Autodesk Fusion 360 part; units mm, degrees
(part 3 of 3)
  line L518 (103.505, 148.65858) -> (102.6922, 148.65858)
  line L519 (137.3378, 134.70636) -> (137.3378, 131.20624)
  line L520 (140.7922, 63.94958) -> (140.7922, 67.4497)
  line L521 (155.575, 76.93914) -> (155.575, 75.9587)
  line L522 (159.8422, 126.43358) -> (159.8422, 129.9337)
  line L523 (122.555, 135.6868) -> (136.525, 135.6868)
  line L524 (137.3378, 131.20624) -> (136.525, 131.20624)
  line L525 (155.575, 67.4497) -> (156.3878, 67.4497)
  line L526 (160.655, 130.91414) -> (174.625, 130.91414)
  line L527 (155.575, 75.9587) -> (156.3878, 75.9587)
  line L528 (155.575, 72.45858) -> (155.575, 67.4497)
  line L529 (136.525, 154.7368) -> (136.525, 153.75636)
  line L530 (136.525, 145.24736) -> (137.3378, 145.24736)
  line L531 (160.655, 126.43358) -> (159.8422, 126.43358)
  line L532 (136.525, 134.70636) -> (137.3378, 134.70636)
  line L533 (103.505, 152.1587) -> (103.505, 153.13914)
  line L534 (140.7922, 67.4497) -> (141.605, 67.4497)
  line L535 (140.7922, 75.9587) -> (141.605, 75.9587)
  line L536 (141.605, 67.4497) -> (141.605, 72.45858)
  line L537 (141.605, 76.93914) -> (155.575, 76.93914)
  line L538 (117.475, 139.16914) -> (103.505, 139.16914)
  line L539 (160.655, 117.92458) -> (159.8422, 117.92458)
  line L540 (118.2878, 152.1587) -> (118.2878, 148.65858)
  line L541 (118.2878, 143.6497) -> (118.2878, 140.14958)
  line L542 (175.4378, 129.9337) -> (175.4378, 126.43358)
  line L543 (174.625, 117.92458) -> (174.625, 116.94414)
  line L544 (117.475, 143.6497) -> (118.2878, 143.6497)
  line L545 (117.475, 148.65858) -> (117.475, 143.6497)
  line L546 (103.505, 140.14958) -> (102.6922, 140.14958)
  line L547 (174.625, 116.94414) -> (160.655, 116.94414)
  line L548 (160.655, 121.4247) -> (160.655, 126.43358)
  line L549 (141.605, 62.96914) -> (141.605, 63.94958)
  line L550 (117.475, 140.14958) -> (117.475, 139.16914)
  line L551 (102.6922, 152.1587) -> (103.505, 152.1587)
  line L552 (102.6922, 143.6497) -> (103.505, 143.6497)
  line L553 (103.505, 143.6497) -> (103.505, 148.65858)
  line L554 (155.575, 63.94958) -> (155.575, 62.96914)
  line L555 (117.475, 152.1587) -> (118.2878, 152.1587)
  line L556 (141.605, 75.9587) -> (141.605, 76.93914)
  line L557 (174.625, 121.4247) -> (175.4378, 121.4247)
  line L558 (103.505, 139.16914) -> (103.505, 140.14958)
  line L559 (174.625, 129.9337) -> (175.4378, 129.9337)
  line L560 (156.3878, 75.9587) -> (156.3878, 72.45858)
  line L561 (175.4378, 117.92458) -> (174.625, 117.92458)
  line L562 (159.8422, 117.92458) -> (159.8422, 121.4247)
  line L563 (136.525, 135.6868) -> (136.525, 134.70636)
  line L564 (118.2878, 148.65858) -> (117.475, 148.65858)
  line L565 (102.6922, 140.14958) -> (102.6922, 143.6497)
  line L566 (141.605, 63.94958) -> (140.7922, 63.94958)
  line L567 (141.605, 72.45858) -> (140.7922, 72.45858)
  line L568 (174.625, 130.91414) -> (174.625, 129.9337)
  line L569 (156.3878, 63.94958) -> (155.575, 63.94958)
  line L570 (159.8422, 121.4247) -> (160.655, 121.4247)
  line L571 (156.3878, 67.4497) -> (156.3878, 63.94958)
  line L572 (159.8422, 129.9337) -> (160.655, 129.9337)
  line L573 (159.8422, 110.8837) -> (160.655, 110.8837)
  line L574 (156.3878, 114.0587) -> (156.3878, 110.55858)
  line L575 (122.555, 122.69724) -> (121.7422, 122.69724)
  line L576 (118.2878, 133.1087) -> (118.2878, 129.60858)
  line L577 (117.475, 121.09958) -> (117.475, 120.11914)
  line L578 (121.7422, 134.70636) -> (122.555, 134.70636)
  line L579 (118.2878, 129.60858) -> (117.475, 129.60858)
  line L580 (160.655, 102.3747) -> (160.655, 107.38358)
  line L581 (121.7422, 131.20624) -> (121.7422, 134.70636)
  line L582 (118.2878, 124.5997) -> (118.2878, 121.09958)
  line L583 (65.405, 151.8666) -> (79.375, 151.8666)
  line L584 (79.375, 138.87704) -> (79.375, 137.8966)
  line L585 (74.89444, 113.27384) -> (74.89444, 114.08664)
  line L586 (65.405, 114.08664) -> (65.405, 128.05664)
  line L587 (66.38544, 113.27384) -> (66.38544, 114.08664)
  line L588 (98.425, 119.82958) -> (98.425, 118.84914)
  line L589 (74.89444, 100.29444) -> (78.39456, 100.29444)
  line L590 (194.4878, 69.28358) -> (193.675, 69.28358)
  line L591 (83.6422, 123.3297) -> (84.455, 123.3297)
  line L592 (69.88556, 128.05664) -> (74.89444, 128.05664)
  line L593 (66.38544, 114.08664) -> (65.405, 114.08664)
  line L594 (78.39456, 84.69884) -> (74.89444, 84.69884)
  line L595 (65.405, 150.88616) -> (65.405, 151.8666)
  line L596 (65.405, 128.05664) -> (66.38544, 128.05664)
  line L597 (78.39456, 100.29444) -> (78.39456, 99.48164)
  line L598 (194.4878, 60.77458) -> (193.675, 60.77458)
  line L599 (79.375, 99.48164) -> (79.375, 85.51164)
  line L600 (69.88556, 84.69884) -> (66.38544, 84.69884)
  line L601 (178.8922, 60.77458) -> (178.8922, 64.2747)
  line L602 (179.705, 59.79414) -> (179.705, 60.77458)
  line L603 (178.8922, 69.28358) -> (178.8922, 72.7837)
  line L604 (98.425, 131.8387) -> (99.2378, 131.8387)
  line L605 (84.455, 131.8387) -> (84.455, 132.81914)
  line L606 (98.425, 128.33858) -> (98.425, 123.3297)
  line L607 (80.1878, 142.37716) -> (80.1878, 138.87704)
  line L608 (78.39456, 85.51164) -> (78.39456, 84.69884)
  line L609 (194.4878, 64.2747) -> (194.4878, 60.77458)
  line L610 (69.88556, 85.51164) -> (69.88556, 84.69884)
  line L611 (69.88556, 128.86944) -> (69.88556, 128.05664)
  line L612 (193.675, 73.76414) -> (193.675, 72.7837)
  line L613 (83.6422, 128.33858) -> (83.6422, 131.8387)
  line L614 (69.88556, 100.29444) -> (69.88556, 99.48164)
  line L615 (46.54042, 57.84342) -> (47.27702, 58.18632)
  line L616 (179.705, 64.2747) -> (179.705, 69.28358)
  line L617 (83.6422, 131.8387) -> (84.455, 131.8387)
  line L618 (50.13706, 50.13198) -> (50.87366, 50.47488)
  line L619 (52.0319, 46.07052) -> (39.37, 40.16502)
  line L620 (39.37, 40.16502) -> (38.95598, 41.05402)
  line L621 (38.21938, 40.71112) -> (36.73856, 43.88358)
  line L622 (84.455, 118.84914) -> (84.455, 119.82958)
  line L623 (99.2378, 123.3297) -> (99.2378, 119.82958)
  line L624 (84.455, 128.33858) -> (83.6422, 128.33858)
  line L625 (38.95598, 41.05402) -> (38.21938, 40.71112)
  line L626 (193.675, 59.79414) -> (179.705, 59.79414)
  line L627 (79.375, 85.51164) -> (78.39456, 85.51164)
  line L628 (52.35194, 47.30242) -> (51.61534, 46.95952)
  line L629 (99.2378, 131.8387) -> (99.2378, 128.33858)
  line L630 (74.89444, 84.69884) -> (74.89444, 85.51164)
  line L631 (194.4878, 72.7837) -> (194.4878, 69.28358)
  line L632 (193.675, 64.2747) -> (194.4878, 64.2747)
  line L633 (74.89444, 85.51164) -> (69.88556, 85.51164)
  line L634 (84.455, 132.81914) -> (98.425, 132.81914)
  line L635 (98.425, 118.84914) -> (84.455, 118.84914)
  line L636 (50.87366, 50.47488) -> (52.35194, 47.30242)
  line L637 (178.8922, 72.7837) -> (179.705, 72.7837)
  line L638 (46.27118, 23.4442) -> (44.79036, 26.61666)
  line L639 (48.02124, 54.67096) -> (50.13706, 50.13198)
  line L640 (56.07304, 37.40404) -> (58.18886, 32.86506)
  line L641 (60.40374, 30.0355) -> (59.66714, 29.6926)
  line L642 (39.97198, 71.93534) -> (42.0878, 67.39636)
  line L643 (31.32074, 57.4294) -> (30.90672, 58.3184)
  line L644 (46.1264, 58.73242) -> (46.54042, 57.84342)
  line L645 (193.675, 69.28358) -> (193.675, 64.2747)
  line L646 (84.455, 119.82958) -> (83.6422, 119.82958)
  line L647 (99.2378, 128.33858) -> (98.425, 128.33858)
  line L648 (98.425, 132.81914) -> (98.425, 131.8387)
  line L649 (33.4645, 52.82692) -> (46.1264, 58.73242)
  line L650 (179.705, 60.77458) -> (178.8922, 60.77458)
  line L651 (30.90672, 58.3184) -> (30.17012, 57.9755)
  line L652 (58.92546, 33.20796) -> (60.40374, 30.0355)
  line L653 (193.675, 60.77458) -> (193.675, 59.79414)
  line L654 (48.58512, 65.47866) -> (48.1711, 66.36766)
  line L655 (48.1711, 66.36766) -> (47.4345, 66.02476)
  line L656 (56.80964, 37.74694) -> (56.07304, 37.40404)
  line L657 (178.8922, 64.2747) -> (179.705, 64.2747)
  line L658 (84.455, 123.3297) -> (84.455, 128.33858)
  line L659 (47.27702, 58.18632) -> (48.75784, 55.01386)
  line L660 (83.6422, 119.82958) -> (83.6422, 123.3297)
  line L661 (179.705, 73.76414) -> (193.675, 73.76414)
  line L662 (48.75784, 55.01386) -> (48.02124, 54.67096)
  line L663 (66.38544, 84.69884) -> (66.38544, 85.51164)
  line L664 (51.61534, 46.95952) -> (52.0319, 46.07052)
  line L665 (193.675, 72.7837) -> (194.4878, 72.7837)
  line L666 (66.38544, 85.51164) -> (65.405, 85.51164)
  line L667 (98.425, 123.3297) -> (99.2378, 123.3297)
  line L668 (179.705, 72.7837) -> (179.705, 73.76414)
  line L669 (179.705, 69.28358) -> (178.8922, 69.28358)
  line L670 (99.2378, 119.82958) -> (98.425, 119.82958)
  line L671 (41.5163, 35.56) -> (54.1782, 41.4655)
  line L672 (28.6893, 61.14796) -> (29.4259, 61.49086)
  line L673 (30.17012, 57.9755) -> (28.6893, 61.14796)
  line L674 (35.35934, 48.76546) -> (34.62274, 48.42256)
  line L675 (57.97296, 80.3275) -> (57.23636, 79.9846)
  line L676 (34.62274, 48.42256) -> (33.14446, 51.59502)
  line L677 (61.56706, 72.61606) -> (60.83046, 72.27316)
  line L678 (42.0878, 67.39636) -> (42.8244, 67.73926)
  line L679 (60.83046, 72.27316) -> (61.24702, 71.38416)
  line L680 (55.32882, 40.9194) -> (56.80964, 37.74694)
  line L681 (61.24702, 71.38416) -> (48.58512, 65.47866)
  line L682 (55.75554, 83.15706) -> (56.49214, 83.49996)
  line L683 (38.49116, 75.1078) -> (39.22776, 75.4507)
  line L684 (45.52696, 26.95956) -> (43.41114, 31.49854)
  line L685 (33.14446, 51.59502) -> (33.88106, 51.93792)
  line L686 (27.31008, 66.02984) -> (26.57348, 65.68694)
  line L687 (26.57348, 65.68694) -> (25.0952, 68.8594)
  line L688 (43.83786, 73.7362) -> (42.35958, 76.90866)
  line L689 (56.49214, 83.49996) -> (57.97296, 80.3275)
  line L690 (44.79036, 26.61666) -> (45.52696, 26.95956)
  line L691 (41.19626, 34.3281) -> (41.93286, 34.671)
  line L692 (41.93286, 34.671) -> (41.5163, 35.56)
  line L693 (60.0837, 28.8036) -> (47.4218, 22.8981)
  line L694 (59.35218, 75.44562) -> (60.08878, 75.78852)
  line L695 (37.47516, 44.22648) -> (35.35934, 48.76546)
  line L696 (43.56608, 64.2239) -> (43.98264, 63.3349)
  line L697 (25.8318, 69.2023) -> (25.41524, 70.0913)
  line L698 (155.575, 140.14958) -> (155.575, 139.16914)
  line L699 (42.67962, 78.14056) -> (55.34152, 84.04606)
  line L700 (44.57446, 74.0791) -> (43.83786, 73.7362)
  line L701 (25.0952, 68.8594) -> (25.8318, 69.2023)
  line L702 (38.07714, 75.9968) -> (38.49116, 75.1078)
  line L703 (121.7422, 153.75636) -> (122.555, 153.75636)
  line L704 (156.3878, 140.14958) -> (155.575, 140.14958)
  line L705 (29.4259, 61.49086) -> (27.31008, 66.02984)
  line L706 (55.34152, 84.04606) -> (55.75554, 83.15706)
  line L707 (45.95368, 69.19722) -> (46.69028, 69.54012)
  line L708 (140.7922, 143.6497) -> (141.605, 143.6497)
  line L709 (44.30268, 64.5668) -> (43.56608, 64.2239)
  line L710 (155.575, 143.6497) -> (156.3878, 143.6497)
  line L711 (39.22776, 75.4507) -> (40.70858, 72.27824)
  line L712 (54.1782, 41.4655) -> (54.59222, 40.5765)
  line L713 (174.625, 148.98116) -> (175.4378, 148.98116)
  line L714 (122.555, 153.75636) -> (122.555, 154.7368)
  line L715 (122.555, 145.24736) -> (122.555, 150.25624)
  line L716 (43.41114, 31.49854) -> (42.67454, 31.15564)
  line L717 (47.4218, 22.8981) -> (47.00778, 23.7871)
  line L718 (59.66714, 29.6926) -> (60.0837, 28.8036)
  line L719 (42.8244, 67.73926) -> (44.30268, 64.5668)
  line L720 (60.08878, 75.78852) -> (61.56706, 72.61606)
  line L721 (33.88106, 51.93792) -> (33.4645, 52.82692)
  line L722 (57.23636, 79.9846) -> (59.35218, 75.44562)
  line L723 (42.67454, 31.15564) -> (41.19626, 34.3281)
  line L724 (46.69028, 69.54012) -> (44.57446, 74.0791)
  line L725 (121.7422, 150.25624) -> (121.7422, 153.75636)
  line L726 (47.00778, 23.7871) -> (46.27118, 23.4442)
  line L727 (40.70858, 72.27824) -> (39.97198, 71.93534)
  line L728 (47.4345, 66.02476) -> (45.95368, 69.19722)
  line L729 (58.18886, 32.86506) -> (58.92546, 33.20796)
  line L730 (43.98264, 63.3349) -> (31.32074, 57.4294)
  line L731 (25.41524, 70.0913) -> (38.07714, 75.9968)
  line L732 (54.59222, 40.5765) -> (55.32882, 40.9194)
  line L733 (36.73856, 43.88358) -> (37.47516, 44.22648)
  line L734 (137.3378, 150.25624) -> (136.525, 150.25624)
  line L735 (136.525, 150.25624) -> (136.525, 145.24736)
  line L736 (141.605, 153.13914) -> (155.575, 153.13914)
  line L737 (141.605, 139.16914) -> (141.605, 140.14958)
  line L738 (141.605, 148.65858) -> (140.7922, 148.65858)
  line L739 (174.625, 149.9616) -> (174.625, 148.98116)
  line L740 (137.3378, 141.74724) -> (136.525, 141.74724)
  line L741 (122.555, 154.7368) -> (136.525, 154.7368)
  line L742 (156.3878, 148.65858) -> (155.575, 148.65858)
  line L743 (141.605, 152.1587) -> (141.605, 153.13914)
  line L744 (141.605, 140.14958) -> (140.7922, 140.14958)
  line L745 (136.525, 140.7668) -> (122.555, 140.7668)
  line L746 (155.575, 139.16914) -> (141.605, 139.16914)
  line L747 (160.655, 136.97204) -> (159.8422, 136.97204)
  line L748 (122.555, 141.74724) -> (121.7422, 141.74724)
  line L749 (160.655, 140.47216) -> (160.655, 145.48104)
  line L750 (42.35958, 76.90866) -> (43.09618, 77.25156)
  line L751 (174.625, 136.97204) -> (174.625, 135.9916)
  line L752 (155.575, 148.65858) -> (155.575, 143.6497)
  line L753 (103.505, 153.13914) -> (117.475, 153.13914)
  line L754 (174.625, 140.47216) -> (175.4378, 140.47216)
  line L755 (159.8422, 136.97204) -> (159.8422, 140.47216)
  line L756 (160.655, 145.48104) -> (159.8422, 145.48104)
  line L757 (117.475, 153.13914) -> (117.475, 152.1587)
  line L758 (155.575, 153.13914) -> (155.575, 152.1587)
  line L759 (175.4378, 140.47216) -> (175.4378, 136.97204)
  line L760 (175.4378, 148.98116) -> (175.4378, 145.48104)
  line L761 (159.8422, 140.47216) -> (160.655, 140.47216)
  line L762 (175.4378, 145.48104) -> (174.625, 145.48104)
  line L763 (160.655, 148.98116) -> (160.655, 149.9616)
  line L764 (141.605, 143.6497) -> (141.605, 148.65858)
  line L765 (159.8422, 148.98116) -> (160.655, 148.98116)
  line L766 (43.09618, 77.25156) -> (42.67962, 78.14056)
  line L767 (140.7922, 148.65858) -> (140.7922, 152.1587)
  line L768 (160.655, 149.9616) -> (174.625, 149.9616)
  line L769 (175.4378, 136.97204) -> (174.625, 136.97204)
  line L770 (140.7922, 152.1587) -> (141.605, 152.1587)
  line L771 (136.525, 141.74724) -> (136.525, 140.7668)
  line L772 (174.625, 135.9916) -> (160.655, 135.9916)
  line L773 (122.555, 140.7668) -> (122.555, 141.74724)
  line L774 (121.7422, 141.74724) -> (121.7422, 145.24736)
  line L775 (121.7422, 145.24736) -> (122.555, 145.24736)
  line L776 (136.525, 153.75636) -> (137.3378, 153.75636)
  line L777 (156.3878, 143.6497) -> (156.3878, 140.14958)
  line L778 (137.3378, 145.24736) -> (137.3378, 141.74724)
  line L779 (160.655, 135.9916) -> (160.655, 136.97204)
  line L780 (140.7922, 140.14958) -> (140.7922, 143.6497)
  line L781 (159.8422, 145.48104) -> (159.8422, 148.98116)
  line L782 (155.575, 152.1587) -> (156.3878, 152.1587)
  line L783 (97, 172.501588) -> (97, 170.504849)
  line L784 (142.99324, 181.50078) -> (152.2984, 186.6138)
  line L785 (82.59572, 68.86956) -> (69.93382, 62.9666)
  circle A2 centre (18.24931, 72.814188) radius 1.5
  line L786 (12.882887, 69.500077) -> (56.241325, -23.483188)
  line L787 (183.6547, 88.33358) -> (183.6547, 91.8337)
  circle A3 centre (113.474545, 182.168703) radius 1.5
  line L788 (92.7708, 177.5) -> (92.7708, 180)
  line L789 (38.807845, 18.915703) -> (38.807845, 18.915703)
  line L790 (78.62824, 44.31792) -> (91.29014, 50.22342)
  arc A4 (60.721045, 186.613703) -> (53.721045, 179.613703) centre (60.721045, 179.613703) ccw
  line L791 (131, 177.5) -> (131, 172.847)
  circle A5 centre (208.543969, 180.349827) radius 1.5
  line L792 (53.721045, 179.613703) -> (53.721045, 100.725006)
  line L793 (68.834, 186.6138) -> (82.7137, 181.50078)
  line L794 (184.4675, 83.3247) -> (184.4675, 88.33358)
  arc A6 (49.679166, 94.380754) -> (53.721045, 100.725006) centre (46.721045, 100.725006) ccw
  line L795 (141.49324, 181.50078) -> (141.49324, 177.5)
  line L796 (49.679166, 94.380754) -> (16.26893, 78.802635)
  line L797 (214.807845, -20.524881) -> (214.807845, 179.613703)
  circle A7 centre (208.543969, 56.03508) radius 1.5
  line L798 (159.21912, 160) -> (119, 160)
  line L799 (64.14262, 33.91916) -> (62.74562, 36.91128)
  line L800 (123.0122, 186.6138) -> (132.31736, 181.50078)
  line L801 (68.53936, 65.95872) -> (81.19872, 71.86168)
  line L802 (62.74562, 36.91128) -> (75.40752, 42.81424)
  line L803 (92.6846, 47.2313) -> (80.02524, 41.3258)
  line L804 (92.7708, 180) -> (89.5, 180)
  line L805 (141.49324, 181.50078) -> (142.99324, 181.50078)
  line L806 (192, 177.5) -> (141.49324, 177.5)
  line L807 (101.749342, 177.25093) -> (111.648837, 167.351435)
  line L808 (92.7708, 177.5) -> (95.767142, 177.5)
  line L809 (65.3161, 64.45504) -> (66.7131, 61.46292)
  line L810 (95.766352, 169.540887) -> (95.767142, 177.5)
  circle A8 centre (128.137965, 52.628703) radius 1.5
  line L811 (82.7137, 181.50078) -> (83.5, 181.50078)
  line L812 (80, 166.5) -> (92.7708, 166.5)
  arc A9 (214.807845, 179.613703) -> (207.807845, 186.613703) centre (207.807845, 179.613703) ccw
  line L813 (80, 168.5) -> (77.004448, 168.498074)
  circle A10 centre (208.543969, -21.260981) radius 1.5
  line L814 (62.585489, -27.524881) -> (207.807845, -27.524881)
  line L815 (101.749342, 177.25093) -> (97, 172.501588)
  arc A11 (207.807845, -27.524881) -> (214.807845, -20.524881) centre (207.807845, -20.524881) ccw
  line L816 (80, 176.457186) -> (77.003658, 176.457186)
  line L817 (159.21912, 160) -> (159.21912, 158)
  line L818 (77.004448, 168.498074) -> (77.003658, 176.457186)
  line L819 (119, 160) -> (119, 172.847)
  line L820 (97, 170.504849) -> (105.901125, 161.603724)
  line L821 (192, 158) -> (192, 177.5)
  arc A12 (56.241325, -23.483188) -> (62.585489, -27.524881) centre (62.585489, -20.524881) ccw
  line L822 (159.21912, 158) -> (192, 158)
  line L823 (133.79196, 181.50078) -> (133.79196, 177.5)
  circle A13 centre (61.866832, -21.652943) radius 1.5
  line L824 (89.5, 181.50078) -> (83.5, 181.50078)
  line L825 (83.5, 180) -> (89.5, 180)
  constraint perpendicular L16 L824
  constraint perpendicular L491 L825
sketch "ErgoDOX Wrist Rest Case Layer 2 Spacer - Right" plane through (250, 0, 160) normal (0, 0, 1) x (1, 0, 0)
  line L0 (132.291915, 181.500877) -> (142.993195, 181.500877)
  arc A0 (60.721, 186.6138) -> (53.721, 179.6138) centre (60.721, 179.6138) ccw
  line L1 (123.012155, 186.613897) -> (132.317491, 181.50078)
  line L2 (138.501016, 157.505491) -> (120.604302, 157.505491)
  arc A1 (195.465659, 56.984991) -> (196.481659, 58.000991) centre (195.465659, 58.000991) ccw
  line L3 (101.739659, 60.159991) -> (119.451016, 60.159991)
  line L4 (142.993019, 181.50078) -> (152.298355, 186.613897)
  arc A2 (57.163855, 86.825015) -> (55.813666, 87.316444) centre (56.243046, 86.395635) ccw
  line L5 (158.889659, 56.984991) -> (195.465659, 56.984991)
  arc A3 (76.628439, 76.003183) -> (76.199059, 77.939991) centre (76.199059, 76.923991) ccw
  line L6 (76.628439, 76.003183) -> (66.166566, 71.124731)
  arc A4 (198.005659, 76.034991) -> (196.481659, 74.510991) centre (198.005659, 74.510991) ccw
  arc A5 (121.805659, 61.747491) -> (120.392873, 60.794991) centre (121.805659, 60.223491) ccw
  line L7 (68.834, 186.6138) -> (60.721, 186.6138)
  arc A6 (16.268885, 78.802732) -> (12.882842, 69.500174) centre (19.227006, 72.458481) ccw
  arc A7 (84.71856, 77.939991) -> (83.337347, 75.771921) centre (84.71856, 76.415991) ccw
  line L8 (204.9178, 152.742991) -> (159.905659, 152.742991)
  line L9 (139.654302, 60.159991) -> (156.349659, 60.159991)
  line L10 (49.67912, 94.380851) -> (16.268885, 78.802732)
  line L11 (82.7137, 181.50078) -> (90.0571, 181.50078)
  arc A8 (100.723659, 76.415991) -> (99.199659, 77.939991) centre (99.199659, 76.415991) ccw
  arc A9 (100.723659, 61.175991) -> (101.739659, 60.159991) centre (101.739659, 61.175991) ccw
  arc A10 (139.442873, 156.870491) -> (140.855659, 155.917991) centre (140.855659, 157.441991) ccw
  line L12 (157.873659, 58.635991) -> (157.873659, 58.000991)
  line L13 (97.937582, 44.461616) -> (83.337347, 75.771921)
  line L14 (158.381659, 154.266991) -> (158.381659, 154.901991)
  line L15 (157.365659, 155.917991) -> (140.855659, 155.917991)
  arc A11 (138.712445, 60.794991) -> (137.299659, 61.747491) centre (137.299659, 60.223491) ccw
  line L16 (62.623659, 153.631991) -> (62.611, 88.3158)
  arc A12 (97.446153, 43.111427) -> (97.937582, 44.461616) centre (97.016773, 44.032236) ccw
  line L17 (22.173124, 70.508569) -> (45.681687, 20.094293)
  circle A13 centre (59.991226, 180.349924) radius 1.5
  line L18 (53.721, 179.6138) -> (53.721, 100.725102)
  circle A14 centre (113.4745, 182.1688) radius 1.5
  line L19 (84.71856, 77.939991) -> (99.199659, 77.939991)
  line L20 (100.723659, 76.415991) -> (100.723659, 61.175991)
  arc A15 (138.712445, 60.794991) -> (139.654302, 60.159991) centre (139.654302, 61.175991) ccw
  line L21 (68.834, 186.6138) -> (82.7137, 181.50078)
  arc A16 (157.873659, 58.000991) -> (158.889659, 56.984991) centre (158.889659, 58.000991) ccw
  arc A17 (119.451016, 60.159991) -> (120.392873, 60.794991) centre (119.451016, 61.175991) ccw
  line L22 (196.481659, 58.000991) -> (196.481659, 74.510991)
  arc A18 (45.681687, 20.094293) -> (47.031876, 19.602864) centre (46.602496, 20.523673) ccw
  line L23 (207.8078, 186.6138) -> (152.298179, 186.6138)
  line L24 (121.805659, 61.747491) -> (137.299659, 61.747491)
  arc A19 (214.8078, 179.6138) -> (207.8078, 186.6138) centre (207.8078, 179.6138) ccw
  circle A20 centre (18.249265, 72.814285) radius 1.5
  arc A21 (139.442873, 156.870491) -> (138.501016, 157.505491) centre (138.501016, 156.489491) ccw
  circle A22 centre (208.543924, 56.035176) radius 1.5
  arc A23 (49.67912, 94.380851) -> (53.721, 100.725102) centre (46.721, 100.725102) ccw
  line L25 (55.813666, 87.316444) -> (22.664552, 71.858758)
  line L26 (47.031876, 19.602864) -> (97.446153, 43.111427)
  arc A24 (158.381659, 154.901991) -> (157.365659, 155.917991) centre (157.365659, 154.901991) ccw
  arc A25 (62.623659, 78.955991) -> (63.639659, 77.939991) centre (63.639659, 78.955991) ccw
  line L27 (192, 177.5) -> (131, 177.5)
  circle A26 centre (128.137965, 52.628703) radius 1.5
  circle A27 centre (208.543924, 180.349924) radius 1.5
  line L28 (205.9178, 77.034991) -> (205.9178, 151.742991)
  arc A28 (157.873659, 58.635991) -> (156.349659, 60.159991) centre (156.349659, 58.635991) ccw
  arc A29 (158.381659, 154.266991) -> (159.905659, 152.742991) centre (159.905659, 154.266991) ccw
  line L29 (64.141282, 71.861874) -> (57.163855, 86.825015)
  arc A30 (64.141282, 71.861874) -> (66.166566, 71.124731) centre (65.522495, 72.505944) ccw
  arc A31 (22.664552, 71.858758) -> (22.173124, 70.508569) centre (23.093932, 70.93795) ccw
  line L30 (198.005659, 76.034991) -> (204.9178, 76.034991)
  line L31 (159.21912, 160) -> (119, 160)
  line L32 (119, 172.847) -> (131, 172.847)
  circle A32 centre (61.866787, -21.652846) radius 1.5
  line L33 (123.012331, 186.6138) -> (103.9368, 186.6138)
  arc A33 (118.249659, 155.917991) -> (119.662445, 156.870491) centre (118.249659, 157.441991) ccw
  line L34 (63.639659, 77.939991) -> (76.199059, 77.939991)
  line L35 (159.21912, 160) -> (159.21912, 158)
  arc A34 (207.8078, -27.524784) -> (214.8078, -20.524784) centre (207.8078, -20.524784) ccw
  line L36 (192, 158) -> (192, 177.5)
  line L37 (159.21912, 158) -> (192, 158)
  line L38 (80, 166.5) -> (92.7708, 166.5)
  line L39 (80, 180) -> (80, 166.5)
  circle A35 centre (208.543924, -21.260884) radius 1.5
  arc A36 (56.24128, -23.483091) -> (62.585444, -27.524784) centre (62.585444, -20.524784) ccw
  line L40 (131, 177.5) -> (131, 172.847)
  line L41 (62.585444, -27.524784) -> (207.8078, -27.524784)
  line L42 (90.0571, 181.50078) -> (103.9368, 186.6138)
  arc A37 (101.399363, 155.917991) -> (100.519481, 155.409991) centre (101.399363, 154.901991) ccw
  line L43 (62.623659, 153.631991) -> (62.623659, 78.955991)
  line L44 (119, 160) -> (119, 172.847)
  arc A38 (204.9178, 76.034991) -> (205.9178, 77.034991) centre (204.9178, 77.034991) ccw
  line L45 (99.199659, 154.647991) -> (63.639659, 154.647991)
  line L46 (38.8078, 18.9158) -> (38.8078, 18.9158)
  line L47 (118.249659, 155.917991) -> (101.399363, 155.917991)
  line L48 (214.8078, -20.524784) -> (214.8078, 179.6138)
  arc A39 (63.639659, 154.647991) -> (62.623659, 153.631991) centre (63.639659, 153.631991) ccw
  line L49 (12.882842, 69.500174) -> (56.24128, -23.483091)
  arc A40 (120.604302, 157.505491) -> (119.662445, 156.870491) centre (120.604302, 156.489491) ccw
  line L50 (92.7708, 180) -> (80, 180)
  arc A41 (99.199659, 154.647991) -> (100.519481, 155.409991) centre (99.199659, 156.171991) ccw
  arc A42 (205.9178, 151.742991) -> (204.9178, 152.742991) centre (204.9178, 151.742991) ccw
  line L51 (92.7708, 166.5) -> (92.7708, 180)
sketch "ErgoDOX Wrist Rest Case Layer 1 Top - Right" plane through (250, 0, 160) normal (0, 0, 1) x (1, 0, 0)
  arc A0 (16.268885, 78.802732) -> (12.882842, 69.500174) centre (19.227006, 72.458481) ccw
  arc A1 (119.451016, 60.159991) -> (120.392873, 60.794991) centre (119.451016, 61.175991) ccw
  line L0 (100.723659, 76.415991) -> (100.723659, 61.175991)
  arc A2 (138.712445, 60.794991) -> (139.654302, 60.159991) centre (139.654302, 61.175991) ccw
  arc A3 (214.8078, 179.6138) -> (207.8078, 186.6138) centre (207.8078, 179.6138) ccw
  line L1 (121.805659, 61.747491) -> (137.299659, 61.747491)
  arc A4 (76.628439, 76.003183) -> (76.199059, 77.939991) centre (76.199059, 76.923991) ccw
  arc A5 (195.465659, 56.984991) -> (196.481659, 58.000991) centre (195.465659, 58.000991) ccw
  arc A6 (158.381659, 154.266991) -> (159.905659, 152.742991) centre (159.905659, 154.266991) ccw
  circle A7 centre (208.543924, 180.349924) radius 1.5
  arc A8 (60.721, 186.6138) -> (53.721, 179.6138) centre (60.721, 179.6138) ccw
  line L2 (158.889659, 56.984991) -> (195.465659, 56.984991)
  line L3 (49.67912, 94.380851) -> (16.268885, 78.802732)
  line L4 (157.873659, 58.635991) -> (157.873659, 58.000991)
  arc A9 (100.723659, 61.175991) -> (101.739659, 60.159991) centre (101.739659, 61.175991) ccw
  line L5 (207.8078, 186.6138) -> (60.721, 186.6138)
  line L6 (196.481659, 58.000991) -> (196.481659, 74.510991)
  circle A10 centre (128.13792, 52.6288) radius 1.907408
  circle A11 centre (59.991226, 180.349924) radius 1.5
  line L7 (55.813666, 87.316444) -> (22.664552, 71.858758)
  arc A12 (97.446153, 43.111427) -> (97.937582, 44.461616) centre (97.016773, 44.032236) ccw
  line L8 (101.739659, 60.159991) -> (119.451016, 60.159991)
  circle A13 centre (18.249265, 72.814285) radius 1.5
  arc A14 (138.712445, 60.794991) -> (137.299659, 61.747491) centre (137.299659, 60.223491) ccw
  line L9 (53.721, 179.6138) -> (53.721, 100.725102)
  arc A15 (45.681687, 20.094293) -> (47.031876, 19.602864) centre (46.602496, 20.523673) ccw
  arc A16 (57.163855, 86.825015) -> (55.813666, 87.316444) centre (56.243046, 86.395635) ccw
  arc A17 (22.664552, 71.858758) -> (22.173124, 70.508569) centre (23.093932, 70.93795) ccw
  arc A18 (198.005659, 76.034991) -> (196.481659, 74.510991) centre (198.005659, 74.510991) ccw
  line L10 (76.628439, 76.003183) -> (66.166566, 71.124731)
  line L11 (64.141282, 71.861874) -> (57.163855, 86.825015)
  arc A19 (84.71856, 77.939991) -> (83.337347, 75.771921) centre (84.71856, 76.415991) ccw
  line L12 (139.654302, 60.159991) -> (156.349659, 60.159991)
  line L13 (62.585444, -27.524784) -> (207.8078, -27.524784)
  line L14 (84.71856, 77.939991) -> (99.199659, 77.939991)
  line L15 (47.031876, 19.602864) -> (97.446153, 43.111427)
  line L16 (198.005659, 76.034991) -> (204.9178, 76.034991)
  line L17 (97.937582, 44.461616) -> (83.337347, 75.771921)
  arc A20 (139.442873, 156.870491) -> (138.501016, 157.505491) centre (138.501016, 156.489491) ccw
  arc A21 (62.623659, 78.955991) -> (63.639659, 77.939991) centre (63.639659, 78.955991) ccw
  arc A22 (205.9178, 151.742991) -> (204.9178, 152.742991) centre (204.9178, 151.742991) ccw
  arc A23 (56.24128, -23.483091) -> (62.585444, -27.524784) centre (62.585444, -20.524784) ccw
  arc A24 (139.442873, 156.870491) -> (140.855659, 155.917991) centre (140.855659, 157.441991) ccw
  line L18 (118.249659, 155.917991) -> (101.399363, 155.917991)
  arc A25 (207.8078, -27.524784) -> (214.8078, -20.524784) centre (207.8078, -20.524784) ccw
  circle A26 centre (208.543924, -21.260884) radius 1.5
  arc A27 (100.723659, 76.415991) -> (99.199659, 77.939991) centre (99.199659, 76.415991) ccw
  arc A28 (204.9178, 76.034991) -> (205.9178, 77.034991) centre (204.9178, 77.034991) ccw
  line L19 (205.9178, 77.034991) -> (205.9178, 151.742991)
  line L20 (158.381659, 154.266991) -> (158.381659, 154.901991)
  line L21 (138.501016, 157.505491) -> (120.604302, 157.505491)
  circle A29 centre (187.2078, 168.6138) radius 1.5
  line L22 (22.173124, 70.508569) -> (45.681687, 20.094293)
  arc A30 (101.399363, 155.917991) -> (100.519481, 155.409991) centre (101.399363, 154.901991) ccw
  arc A31 (64.141282, 71.861874) -> (66.166566, 71.124731) centre (65.522495, 72.505944) ccw
  line L23 (214.8078, -20.524784) -> (214.8078, 179.6138)
  line L24 (204.9178, 152.742991) -> (159.905659, 152.742991)
  arc A32 (157.873659, 58.000991) -> (158.889659, 56.984991) centre (158.889659, 58.000991) ccw
  circle A33 centre (113.474545, 182.168703) radius 1.5
  line L25 (38.8078, 18.9158) -> (38.8078, 18.9158)
  arc A34 (99.199659, 154.647991) -> (100.519481, 155.409991) centre (99.199659, 156.171991) ccw
  arc A35 (121.805659, 61.747491) -> (120.392873, 60.794991) centre (121.805659, 60.223491) ccw
  arc A36 (157.873659, 58.635991) -> (156.349659, 60.159991) centre (156.349659, 58.635991) ccw
  circle A37 centre (208.543924, 56.035176) radius 1.5
  line L26 (99.199659, 154.647991) -> (63.639659, 154.647991)
  line L27 (62.623659, 153.631991) -> (62.611, 88.3158)
  arc A38 (49.67912, 94.380851) -> (53.721, 100.725102) centre (46.721, 100.725102) ccw
  line L28 (12.882842, 69.500174) -> (56.24128, -23.483091)
  line L29 (63.639659, 77.939991) -> (76.199059, 77.939991)
  circle A39 centre (61.866787, -21.652846) radius 1.5
  arc A40 (120.604302, 157.505491) -> (119.662445, 156.870491) centre (120.604302, 156.489491) ccw
  arc A41 (158.381659, 154.901991) -> (157.365659, 155.917991) centre (157.365659, 154.901991) ccw
  line L30 (62.623659, 153.631991) -> (62.623659, 78.955991)
  arc A42 (63.639659, 154.647991) -> (62.623659, 153.631991) centre (63.639659, 153.631991) ccw
  line L31 (157.365659, 155.917991) -> (140.855659, 155.917991)
  arc A43 (118.249659, 155.917991) -> (119.662445, 156.870491) centre (118.249659, 157.441991) ccw
sketch "ErgoDOX Case Layer 4 Spacer - Left" plane through (0, 0, 0) normal (0, 0, 1) x (1, 0, 0)
  line L0 (196, 16) -> (196, 16)
  circle A0 centre (26.263876, 53.119376) radius 1.25
  circle A1 centre (174.816574, 177.434124) radius 1.25
  arc A2 (20, -23.440584) -> (27, -30.440584) centre (27, -23.440584) ccw
  line L1 (152.0941, 178.58498) -> (144.7507, 178.58498)
  circle A3 centre (26.263876, -24.176684) radius 1.25
  circle A4 centre (26.263876, 177.434124) radius 1.25
  arc A5 (221.924958, 66.584374) -> (218.538915, 75.886932) centre (215.580794, 69.542681) ccw
  circle A6 centre (216.558535, 69.898485) radius 1.25
  line L2 (144.7507, 178.58498) -> (130.871, 183.698)
  arc A7 (27, 183.698) -> (20, 176.698) centre (27, 176.698) ccw
  line L3 (165.9738, 183.698) -> (152.0941, 178.58498)
  line L4 (165.9738, 183.698) -> (174.0868, 183.698)
  line L5 (20, -23.440584) -> (20, 176.698)
  circle A8 centre (106.66988, 49.713) radius 1.25
  arc A9 (172.222356, -30.440584) -> (178.56652, -26.398891) centre (172.222356, -23.440584) ccw
  line L6 (221.924958, 66.584374) -> (178.56652, -26.398891)
  line L7 (196, 16) -> (196, 16)
  arc A10 (181.0868, 97.809302) -> (185.12868, 91.465051) centre (188.0868, 97.809302) ccw
  line L8 (185.12868, 91.465051) -> (218.538915, 75.886932)
  line L9 (172.222356, -30.440584) -> (27, -30.440584)
  arc A11 (181.0868, 176.698) -> (174.0868, 183.698) centre (174.0868, 176.698) ccw
  line L10 (181.0868, 176.698) -> (181.0868, 97.809302)
  line L11 (27, 183.698) -> (130.871, 183.698)
  circle A12 centre (121.3333, 179.253) radius 1.25
  circle A13 centre (172.941013, -24.568646) radius 1.25
  line L12 (196, 16) -> (196, 16)
  line L13 (173.1968, 172.049549) -> (173.1968, 86.4)
  line L14 (173.1968, 86.4) -> (177.320693, 86.4)
  line L15 (177.320693, 86.4) -> (210.988017, 70.700814)
  line L16 (210.988017, 70.700814) -> (212.808239, 65.703476)
  line L17 (212.808239, 65.703476) -> (190.774025, 18.450062)
  line L18 (190.774025, 18.450062) -> (185.776569, 16.632805)
  line L19 (185.776569, 16.632805) -> (107.433742, 53.158)
  line L20 (107.433742, 53.158) -> (38.000786, 53.158)
  line L21 (38.000786, 53.158) -> (27.89, 63.268786)
  line L22 (27.89, 63.268786) -> (27.89, 172.047214)
  line L23 (27.89, 172.047214) -> (31.650786, 175.808)
  line L24 (31.650786, 175.808) -> (90.3994, 175.808)
  line L25 (90.3994, 175.808) -> (90.3994, 177.586)
  line L26 (90.3994, 177.586) -> (103.9056, 177.586)
  line L27 (103.9056, 177.586) -> (103.9056, 175.808)
  line L28 (103.9056, 175.808) -> (138.761, 175.808)
  line L29 (138.761, 175.808) -> (138.761, 177.586)
  line L30 (138.761, 177.586) -> (157.9314, 177.586)
  line L31 (157.9314, 177.586) -> (157.9314, 175.808)
  line L32 (157.9314, 175.808) -> (169.408282, 175.808)
  line L33 (169.408282, 175.808) -> (173.1968, 172.049549)
  dimension "d38" = 2.5
  constraint equal A1 A12
  constraint equal A1 A4
  constraint equal A1 A6
  constraint equal A1 A8
  constraint equal A0 A1
  constraint equal A1 A13
  constraint equal A1 A3
  measures "d38" diameter of A1
extrude "Extrude10" add sketch "ErgoDOX Case Layer 5 Bottom - Left" sketch "ErgoDOX Wrist Rest Case Layer 5 Bottom - Right" against normal blind 2 contours A0 L1 A1 A2 A3 A4 L3 A5 L4 L5 L6 L7 picked at (73.719023, 83.359119) of sketch 2 contours L0 L1 L2 L3 A0 A1 A2 A3 L5 A4 A5 L6 picked at (161.088777, 86.274919) makes body 1 at (73.719023, 83.359119, 0) makes body 2 at (411.088777, 86.274919, 0)
extrude "Extrude11" add sketch "ErgoDOX Wrist Rest Case Layer 4 Spacer - Right" sketch "ErgoDOX Case Layer 4 Spacer - Left" along normal blind 4 contours L1 L2 L3 L4 L5 L6 A5 L7 L8 L9 A6 L10 L11 L12 A10 L13 L14 A11 A12 A13 picked at (132.942261, 2.832137) of sketch 2 contours A2 L1 A5 L2 A7 L3 L4 L5 A9 L6 A10 L8 L9 A11 L10 L11 picked at (101.865539, -0.083663) bodies 1 2
extrude "Extrude12" add sketch "ErgoDOX Wrist Rest Case Layer 3 Plate - Right" sketch "ErgoDOX Case Layer 3 Plate - Left" along normal blind 5 separate body contours L16 L290 L291 L292 L296 L298 L299 L300 L301 L302 L303 L491 L493 L495 L496 A1 L784 L786 L788 A4 L791 L792 L793 A6 L795 L796 L797 L798 L800 L804 L805 L806 L808 L810 L811 L812 A9 L813 L814 A11 L816 L817 L818 L819 L821 A12 L822 L823 picked at (132.849589, 2.73826) of sketch 2 contours L592 L602 A2 A4 A6 L614 L620 L621 L622 L626 L628 A9 L643 L644 L646 A10 L648 L649 L651 L652 L653 L655 A12 L656 L657 L658 L659 L660 L661 L663 L664 L665 picked at (101.958257, -0.177443) makes body 3 at (382.849589, 2.73826, 85) makes body 4 at (101.958257, -0.177443, 85)
extrude "Extrude13" add sketch "ErgoDOX Case Layer 2 Spacer - Left" sketch "ErgoDOX Wrist Rest Case Layer 2 Spacer - Right" against normal blind 4 separate body contours A0 A6 L2 L3 L4 A11 L10 L11 L14 L16 L18 L20 L24 A27 A28 A39 L40 L42 picked at (101.958256, -0.177443) of sketch 2 contours L0 A0 L1 L4 L7 A6 L10 L11 L18 L21 L23 A19 A23 L33 A34 A36 L41 L42 L48 L49 picked at (132.849559, 2.738324) makes body 5 at (101.958256, -0.177443, 160) makes body 6 at (382.849559, 2.738324, 160)
extrude "Extrude14" add sketch "ErgoDOX Case Layer 1 Top - Left" sketch "ErgoDOX Wrist Rest Case Layer 1 Top - Right" along normal blind 2 contours L0 L1 A1 L4 A4 L8 L10 L14 A18 A26 A33 A42 picked at (101.958256, -0.177443) of sketch 2 contours A0 A3 A8 L3 L5 L9 L13 A23 A25 L23 A38 L28 picked at (132.897057, 2.604332) bodies 5 6
chamfer "Chamfer6" distance 0.6 angle 45 16 edges at (25.098467, 177.886143, 4) (120.167891, 179.705019, 4) (173.651165, 177.886143, 4) (215.393126, 70.350504, 4) (105.504471, 50.165019, 4) (25.098467, 53.571396, 4) (25.098467, -23.724665, 4) (171.775604, -24.116627, 4) (308.825817, 180.801943, 4) (362.309091, 182.620819, 4) (457.378515, 180.801943, 4) (457.378515, 56.487196, 4) (376.972511, 53.080819, 4) (267.083856, 73.266304, 4) (310.701377, -21.200827, 4) (457.378515, -20.808865, 4) on bodies 1 2
chamfer "Chamfer7" distance 2 angle 45 16 edges at (24.865385, 177.976547, 162) (119.934809, 179.795423, 162) (173.418083, 177.976547, 162) (24.865385, 53.661799, 162) (105.271389, 50.255423, 162) (215.160044, 70.440908, 162) (171.542522, -24.026223, 162) (24.865385, -23.634261, 162) (308.592735, 180.892347, 162) (362.076054, 182.711126, 162) (457.145433, 180.892347, 162) (457.145433, 56.577599, 162) (376.359591, 53.318548, 162) (266.850774, 73.356708, 162) (310.468296, -21.110423, 162) (457.145433, -20.718461, 162) on bodies 5 6
extrude "Extrude18" cut sketch "ErgoDOX Wrist Rest Case Layer 3 Plate - Right" sketch "ErgoDOX Case Layer 3 Plate - Left" along normal blind 72 contours L16 L491 L824 L825 picked at (87.5, 181.00052) of sketch 2 contours L649 L651 L814 L815 picked at (147.537046, 178.084817) bodies 5 6
extrude "Extrude19" cut 1 faces at (147.537046, 177.084297, 156.333333) along direction (0, -1, 0) blind 1 on bodies 5 bodies 5
extrude "Extrude20" cut sketch "ErgoDOX Wrist Rest Case Layer 3 Plate - Right" sketch "ErgoDOX Case Layer 3 Plate - Left" against normal blind 82 contours L16 L491 L824 L825 picked at (87.5, 181.00052) of sketch 2 contours L649 L651 L814 L815 picked at (147.537046, 178.084817) bodies 1 2
ref_plane "WorkPlane3" through (0, 0, 260) normal (0, 0, 1) x (1, 0, 0)
sketch "ErgoDOX Case Layer 5 Bottom - Left (1)" plane through (0, 0, 260) normal (0, 0, 1) x (1, 0, 0)
  line L0 (185.12868, 91.465051) -> (218.538915, 75.886932)
  arc A0 (107.090611, 44.612392) -> (104.132792, 45.268) centre (104.132792, 38.268) ccw
  line L1 (104.132792, 45.268) -> (27, 45.268)
  circle A1 centre (189.972097, 12.882405) radius 1.5
  arc A2 (221.924958, 66.584374) -> (218.538915, 75.886932) centre (215.580794, 69.542681) ccw
  arc A3 (181.0868, 176.698) -> (174.0868, 183.698) centre (174.0868, 176.698) ccw
  line L2 (196, 16) -> (196, 16)
  line L3 (181.0868, 176.698) -> (181.0868, 97.809302)
  line L4 (221.924958, 66.584374) -> (195.960572, 10.903092)
  line L5 (196, 16) -> (196, 16)
  arc A4 (181.0868, 97.809302) -> (185.12868, 91.465051) centre (188.0868, 97.809302) ccw
  line L6 (186.658589, 7.517007) -> (107.090611, 44.612392)
  line L7 (27, 183.698) -> (174.0868, 183.698)
  arc A5 (20, 52.268) -> (27, 45.268) centre (27, 52.268) ccw
  arc A6 (186.658589, 7.517007) -> (195.960572, 10.903092) centre (189.616408, 13.861399) ccw
  arc A7 (27, 183.698) -> (20, 176.698) centre (27, 176.698) ccw
  line L8 (20, 52.268) -> (20, 176.698)
sketch "ErgoDOX Case Layer 5 Bottom - Right" plane through (250, 0, 260) normal (0, 0, 1) x (1, 0, 0)
  arc A0 (49.67912, 94.380851) -> (53.721, 100.725102) centre (46.721, 100.725102) ccw
  arc A1 (207.8078, 48.1838) -> (214.8078, 55.1838) centre (207.8078, 55.1838) ccw
  arc A2 (214.8078, 179.6138) -> (207.8078, 186.6138) centre (207.8078, 179.6138) ccw
  line L0 (214.8078, 55.1838) -> (214.8078, 179.6138)
  line L1 (48.149211, 10.432807) -> (127.71719, 47.528192)
  line L2 (12.882842, 69.500174) -> (38.847228, 13.818892)
  line L3 (130.675008, 48.1838) -> (207.8078, 48.1838)
  line L4 (53.721, 179.6138) -> (53.721, 100.725102)
  arc A3 (130.675008, 48.1838) -> (127.717189, 47.528192) centre (130.675008, 41.1838) ccw
  circle A4 centre (44.835703, 15.798205) radius 1.5
  line L5 (38.8078, 18.9158) -> (38.8078, 18.9158)
  line L6 (49.67912, 94.380851) -> (16.268885, 78.802732)
  line L7 (207.8078, 186.6138) -> (60.721, 186.6138)
  arc A5 (60.721, 186.6138) -> (53.721, 179.6138) centre (60.721, 179.6138) ccw
  arc A6 (16.268885, 78.802732) -> (12.882842, 69.500174) centre (19.227006, 72.458481) ccw
  arc A7 (38.847228, 13.818892) -> (48.149211, 10.432807) centre (45.191392, 16.777199) ccw
extrude "Extrude21" cut sketch "ErgoDOX Case Layer 5 Bottom - Right" sketch "ErgoDOX Case Layer 5 Bottom - Left (1)" against normal blind 325 contours A0 A1 A2 L0 L1 L2 L3 L4 A3 L6 L7 A5 A6 A7 picked at (130.734603, 111.840901) of sketch 2 contours L0 A0 L1 A2 A3 L3 L4 A4 L6 L7 A5 A6 A7 L8 picked at (104.073197, 108.925101) keep common part bodies 1 2 3 4 5 6
chamfer "Chamfer8" distance 2 angle 45 2 edges at (188.573606, 12.339982, 162) (293.437212, 15.255782, 162) on bodies 5 6
sketch "Sketch16" plane through (0, 0, -2) normal (0, 0, -1) x (-1, 0, 0)
  circle A0 centre (-294.835703, 15.798205) radius 1.5
  arc A1 (-298.149211, 10.432807) -> (-288.847228, 13.818892) centre (-295.191392, 16.777199) ccw
  line L0 (-288.847228, 13.818892) -> (-262.882842, 69.500174)
  arc A2 (-262.882842, 69.500174) -> (-266.268885, 78.802732) centre (-269.227006, 72.458481) ccw
  line L1 (-266.268885, 78.802732) -> (-299.67912, 94.380851)
  arc A3 (-303.721, 100.725102) -> (-299.67912, 94.380851) centre (-296.721, 100.725102) ccw
  line L2 (-303.721, 100.725102) -> (-303.721, 179.6138)
  arc A4 (-303.721, 179.6138) -> (-310.721, 186.6138) centre (-310.721, 179.6138) ccw
  line L3 (-310.721, 186.6138) -> (-457.8078, 186.6138)
  arc A5 (-457.8078, 186.6138) -> (-464.8078, 179.6138) centre (-457.8078, 179.6138) ccw
  line L4 (-464.8078, 179.6138) -> (-464.8078, 55.1838)
  arc A6 (-464.8078, 55.1838) -> (-457.8078, 48.1838) centre (-457.8078, 55.1838) ccw
  line L5 (-457.8078, 48.1838) -> (-380.675008, 48.1838)
  arc A7 (-377.717189, 47.528192) -> (-380.675008, 48.1838) centre (-380.675008, 41.1838) ccw
  line L6 (-377.717189, 47.528192) -> (-298.149211, 10.432807)
  circle A8 centre (-294.835703, 15.798205) radius 1.5
  circle A9 centre (-189.972097, 12.882405) radius 1.5
  circle A10 centre (-189.972097, 12.882405) radius 1.5
  dimension "d67" = 3
  constraint concentric A0 A8
  constraint concentric A9 A10
  measures "d67" diameter of A9
extrude "Extrude22" add sketch "Sketch16" against normal blind 1.6 contours A0 A8 | A9 A10 picked at (-294.523958, 14.973406) picked at (-190.703964, 12.542319) bodies 1 2
chamfer "Chamfer9" distance 0.6 angle 45 122 edges at (170.0303, 183.698, 156) (179.036547, 181.647747, 156) (181.0868, 137.253651, 156) (182.183121, 94.048109, 156) (201.833797, 83.675992, 156) (222.158599, 71.93694, 156) (208.942765, 38.743733, 156) (192.010823, 7.28365, 156) (146.8746, 26.064699, 156) (105.647595, 45.102133, 156) (65.566396, 45.268, 156) (22.050253, 47.318253, 156) (20, 114.483, 156) (22.050253, 181.647747, 156) (78.9355, 183.698, 156) (314.777523, 186.613752, 85) (305.771298, 184.563451, 85) (303.721045, 140.169354, 85) (302.624724, 96.963812, 85) (282.974048, 86.591695, 85) (262.649246, 74.852644, 85) (275.865057, 41.659484, 85) (292.796977, 10.19945, 85) (337.9332, 28.980499, 85) (379.160205, 48.017933, 85) (419.241404, 48.1838, 85) (462.757547, 50.234053, 85) (464.8078, 117.3988, 85) (464.64188, 181.12884, 85) (461.56893, 185.517452, 85) (430.053123, 186.613752, 85) (314.777523, 186.613752, 90) (305.771298, 184.563451, 90) (303.721045, 140.169354, 90) (302.624724, 96.963812, 90) (282.974048, 86.591695, 90) (262.649246, 74.852644, 90) (275.865057, 41.659484, 90) (292.796977, 10.19945, 90) (337.9332, 28.980499, 90) (379.160205, 48.017933, 90) (419.241404, 48.1838, 90) (462.757547, 50.234053, 90) (464.8078, 117.3988, 90) (464.64188, 181.12884, 90) (461.56893, 185.517452, 90) (430.053123, 186.613752, 90) (314.7775, 186.6138, 4) (305.771253, 184.563547, 4) (303.721, 140.169451, 4) (302.624679, 96.963909, 4) (282.974003, 86.591792, 4) (262.649201, 74.85274, 4) (275.865035, 41.659533, 4) (292.796977, 10.19945, 4) (337.9332, 28.980499, 4) (379.160205, 48.017933, 4) (419.241404, 48.1838, 4) (462.757547, 50.234053, 4) (464.8078, 117.3988, 4) (462.757547, 184.563547, 4) (430.052989, 186.6138, 4) (170.030191, 183.698, 85) (179.036548, 181.647748, 85) (181.0868, 137.253651, 85) (182.183122, 94.048109, 85) (201.833798, 83.675992, 85) (222.1586, 71.93694, 85) (208.942765, 38.743733, 85) (192.010823, 7.28365, 85) (146.8746, 26.064699, 85) (105.647595, 45.102133, 85) (65.566396, 45.268, 85) (22.050253, 47.318253, 85) (20, 114.483, 85) (22.050253, 181.647748, 85) (78.935654, 183.698, 85) (78.935654, 183.698, 90) (22.050253, 181.647748, 90) (20, 114.483, 90) (22.050253, 47.318253, 90) (65.566396, 45.268, 90) (105.647595, 45.102133, 90) (146.8746, 26.064699, 90) (192.010823, 7.28365, 90) (208.942765, 38.743733, 90) (222.1586, 71.93694, 90) (201.833798, 83.675992, 90) (182.183122, 94.048109, 90) (181.0868, 137.253651, 90) (179.036548, 181.647748, 90) (170.030191, 183.698, 90) (430.052989, 186.6138, 156) (462.757547, 184.563547, 156) (464.8078, 117.3988, 156) (462.757547, 50.234053, 156) (419.241404, 48.1838, 156) (379.160205, 48.017933, 156) (337.9332, 28.980499, 156) (292.796977, 10.19945, 156) (275.865035, 41.659533, 156) (262.649201, 74.85274, 156) (282.974003, 86.591792, 156) (302.624679, 96.963909, 156) (303.721, 140.169451, 156) (305.771253, 184.563547, 156) (314.7775, 186.6138, 156) (78.9355, 183.698, 4) (22.050253, 181.647747, 4) (20, 114.483, 4) (22.050253, 47.318253, 4) (65.566396, 45.268, 4) (105.647595, 45.102133, 4) (146.8746, 26.064699, 4) (192.010823, 7.28365, 4) (208.942765, 38.743733, 4) (222.158599, 71.93694, 4) (201.833797, 83.675992, 4) (182.183121, 94.048109, 4) (181.0868, 137.253651, 4) (179.036547, 181.647747, 4) (170.0303, 183.698, 4) on bodies 1 2 3 4 5 6
named bodies: "ergodox-left-bottom", "ergodox-right-bottom", "ergodox-right-plate", "ergodox-left-plate", "ergodox-left-top", "ergodox-right-top"
